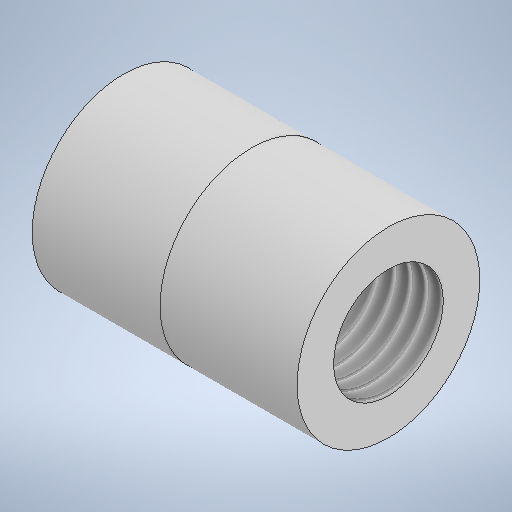
# Autodesk Inventor part: cilindro_ext_pasante
Saved by Autodesk Inventor 2025.2 (Build 292293000, 293)
## iProperties
Created: 2025-03-19
Part Number: cilindro_ext_pasante
Material: Generic
Document SubType Name: Modeling
Designer: laura
Density: 1 g/cm^3
Appearance: Default
Author: laura
Autodesk Inventor part; units mm, degrees
ref_plane "YZ Plane" through (0, 0, 0) normal (1, 0, 0) x (0, 1, 0)
ref_plane "XZ Plane" through (0, 0, 0) normal (0, 1, 0) x (-1, 0, 0)
ref_plane "XY Plane" through (0, 0, 0) normal (0, 0, 1) x (1, 0, 0)
sketch "Sketch1" plane through (0, 0, 0) normal (0, 1, 0) x (-1, 0, 0)
  line L0 (14.5, 0) -> (-14.5, 0)
  line L1 (-14.5, -6) -> (-14.5, -10)
  line L2 (-14.5, -6) -> (-14.5, 0) construction
  line L3 (14.5, -4.75) -> (14.5, 0) construction
  line L4 (-14.5, -10) -> (0.5, -10)
  line L5 (0.5, -10) -> (0.5, -4.75)
  line L6 (0.5, -4.75) -> (14.5, -4.75)
  line L7 (0.5, -10) -> (14.5, -10)
  line L8 (14.5, -10) -> (14.5, -4.75)
  line L9 (-14.5, -6) -> (0.5, -6)
  point P0 (0, 0)
  point P1 (0, 0)
  point P2 (-14.5, -8)
  dimension "d4" = 20
  dimension "d7" = 15
  dimension "d11" = 12
  dimension "d12" = 9.5
  dimension "d15" = 14
  dimension "d16" = 14.5
  constraints: 20 end point, 4 horizontal, 3 vertical, 2 midpoint, 2 perpendicular, 1 coincident, 1 point on line
  measures "d4" diameter of L7 L0
  measures "d7" distance from line of point (-14.5, -8) L5
  measures "d11" diameter of L9 L0
  measures "d12" diameter of L6 L0
  measures "d15" distance between parallel lines of L5 L8
  measures "d16" distance of L0.end point (0, 0)
revolve "Revolution1" add sketch "Sketch1" angle 360 about axis through (-14.5, 0, 0) along (1, 0, 0) contours L5 L6 L8 L7
revolve "Revolution2" add sketch "Sketch1" angle 360 about axis through (-14.5, 0, 0) along (1, 0, 0) separate body contours L9 L5 L4 L1
thread "Thread2" size "M12x1.75" class "6H" standard "ANSI Metric M Profile" full length
body "Solid1"
body "Solid2"
